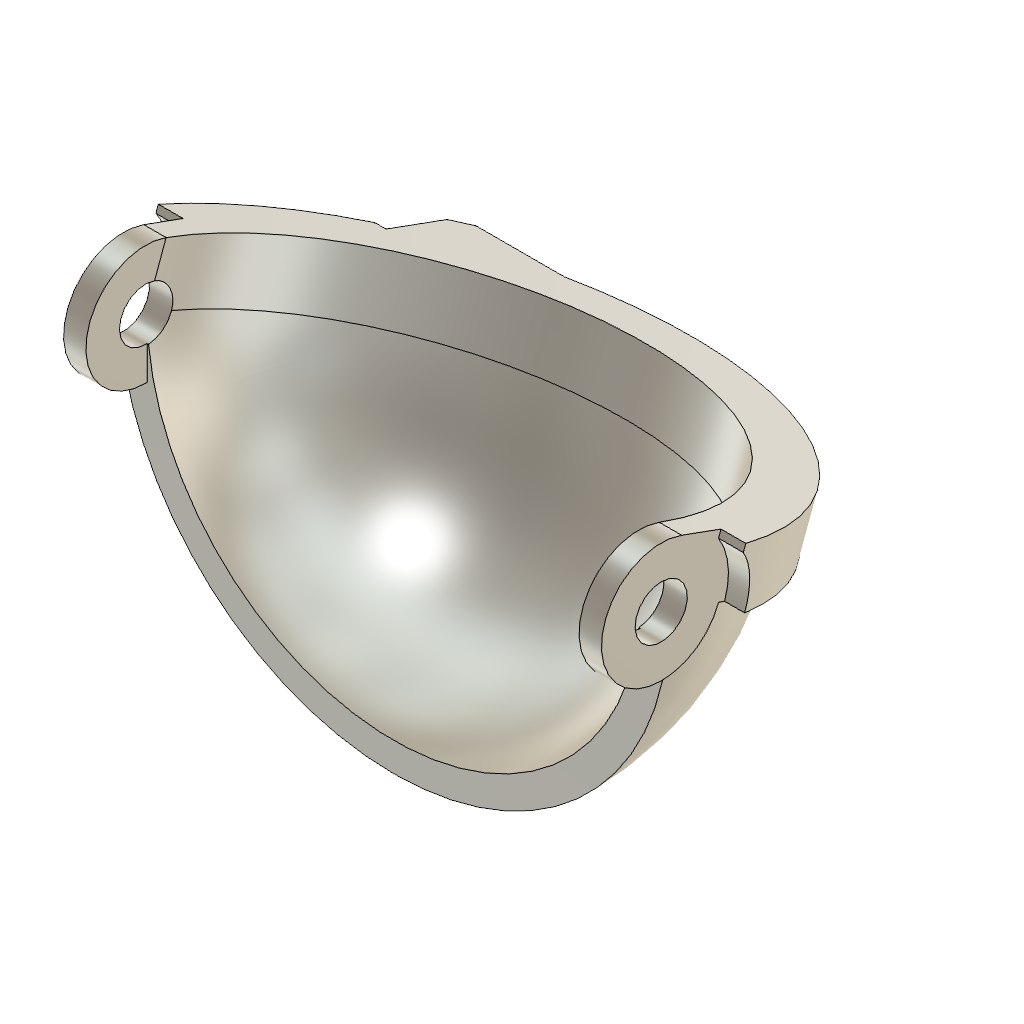
Top Left Lid native (Autodesk Fusion 360 design; units mm, degrees)
part number: 2026-10-13-22-57-52-856
Autodesk Fusion 360 part; units mm, degrees
ref_plane "WorkPlane1" through (0, 0, 2.0171) normal (0, 0, 1) x (1, 0, 0)
sketch "Lip ring" plane through (0, 0, 2.0171) normal (0, 0, 1) x (1, 0, 0)
  circle A0 centre (0, 0) radius 19.858
  dimension "d63" = 39.716
  constraint coincident A0.centre origin
  measures "d63" diameter of A0
extrude "Lip ring (1)" add sketch "Lip ring" along normal mid plane 3.9658
ref_plane "WorkPlane2" through (0, 0, 2.0171) normal (0, 0, 1) x (1, 0, 0)
sketch "Ring bore" plane through (0, 0, 2.0171) normal (0, 0, 1) x (1, 0, 0)
  circle A0 centre (0, 0.094) radius 16.5
  dimension "d64" = 33
  dimension "d65" = 0.094
  constraint vertical origin A0.centre
  measures "d64" diameter of A0
  measures "d65" vertical distance of origin A0.centre
extrude "Ring bore (1)" cut sketch "Ring bore" along normal mid plane 4.9658
ref_plane "WorkPlane3" through (0, 0.094, 0) normal (0, 1, 0) x (0, 0, 1)
sketch "Shell" plane through (0, 0.094, 0) normal (0, 1, 0) x (1, 0, 0)
  line L0 (16.5, -0.5342) -> (18.435, -0.5342)
  line L1 (18.435, -0.5342) -> (18.435, -0.0342)
  arc A0 (18.435, -0.0342) -> (0, 18.4008) centre (0, -0.0342) ccw
  line L2 (0, 18.4008) -> (0, 16.4658)
  arc A1 (16.5, -0.0342) -> (0, 16.4658) centre (0, -0.0342) ccw
  line L3 (16.5, -0.0342) -> (16.5, -0.5342)
  line L4 (0, 18.4008) -> (0, -0.5342) construction
  dimension "d66" = 18.435
  dimension "d67" = 16.5
  dimension "d68" = 0.0342
  dimension "d69" = 0.5342
  dimension "d70" = 18.4008
  dimension "d71" = 0.5342
  constraint horizontal L0
  constraint vertical L1
  constraint vertical L2
  constraint vertical L3
  constraint vertical L4
  constraint tangent L1 A0
  constraint tangent A1 L3
  constraint coincident A0.centre A1.centre
  constraint vertical origin A0.centre
  constraint vertical origin A0.end
  measures "d66" radius of A0
  measures "d67" radius of A1
  measures "d68" vertical distance of origin A0.centre
  measures "d69" vertical distance of origin L0.start
  measures "d70" vertical distance of origin A0.end
  measures "d71" vertical distance of origin L4.end
revolve "Shell (1)" add sketch "Shell" angle 360 about axis through (0, 0.094, -18.4008) along (0, 0, 1)
sketch "Shell trim y0.1" plane through (0, 0, 0) normal (1, 0, 0) x (0, 0, -1)
  line L0 (25, 9.2057) -> (-25, -8.9928)
  line L1 (-25, -8.9928) -> (-25, -30)
  line L2 (-25, -30) -> (25, -30)
  line L3 (25, -30) -> (25, 9.2057)
  dimension "d72" = 25
  dimension "d73" = 9.2057
  dimension "d74" = 25
  dimension "d75" = 8.9928
  dimension "d76" = 30
  constraint vertical L1
  constraint horizontal L2
  constraint vertical L3
  measures "d72" horizontal distance of origin L0.start
  measures "d73" vertical distance of origin L0.start
  measures "d74" horizontal distance of origin L0.end
  measures "d75" vertical distance of origin L0.end
  measures "d76" vertical distance of origin L1.end
extrude "Shell trim y0.1 (1)" cut sketch "Shell trim y0.1" along normal mid plane 42
ref_plane "WorkPlane4" through (0, 0, 2.0171) normal (0, 0, 1) x (1, 0, 0)
sketch "Ring half" plane through (0, 0, 2.0171) normal (0, 0, 1) x (1, 0, 0)
  line L0 (-21, 0) -> (21, 0)
  line L1 (21, 0) -> (21, -21)
  line L2 (21, -21) -> (-21, -21)
  line L3 (-21, -21) -> (-21, 0)
  dimension "d77" = 21
  dimension "d78" = 21
  dimension "d79" = 21
  constraint horizontal L0
  constraint vertical L1
  constraint horizontal L2
  constraint vertical L3
  constraint horizontal origin L0.start
  measures "d77" horizontal distance of origin L0.start
  measures "d78" horizontal distance of origin L0.end
  measures "d79" vertical distance of origin L1.end
extrude "Ring half (1)" cut sketch "Ring half" along normal mid plane 4.9658
ref_plane "WorkPlane5" through (19.5, 0, 0) normal (1, 0, 0) x (0, 1, 0)
sketch "Past ear R" plane through (19.5, 0, 0) normal (1, 0, 0) x (0, 0, -1)
  line L0 (6, -6) -> (6, 2.8)
  line L1 (6, 2.8) -> (3.5228, 2.8)
  arc A0 (3.5228, 2.8) -> (-3.5228, 2.8) centre (0, 0) ccw
  line L2 (-3.5228, 2.8) -> (-4.5, 2.8)
  line L3 (-4.5, 2.8) -> (-4.5, -6)
  line L4 (-4.5, -6) -> (6, -6)
  dimension "d80" = 4.5
  dimension "d81" = 6
  dimension "d82" = 6
  dimension "d83" = 2.8
  dimension "d84" = 3.5228
  dimension "d85" = 4.5
  constraint vertical L0
  constraint horizontal L1
  constraint horizontal L2
  constraint vertical L3
  constraint horizontal L4
  constraint coincident A0.centre origin
  measures "d80" radius of A0
  measures "d81" horizontal distance of A0.centre L0.start
  measures "d82" vertical distance of A0.centre L0.start
  measures "d83" vertical distance of A0.centre L0.end
  measures "d84" horizontal distance of A0.centre A0.end
  measures "d85" horizontal distance of A0.centre L2.end
extrude "Past ear R (1)" cut sketch "Past ear R" along normal mid plane 3
ref_plane "WorkPlane6" through (-19.5, 0, 0) normal (1, 0, 0) x (0, 1, 0)
sketch "Past ear L" plane through (-19.5, 0, 0) normal (1, 0, 0) x (0, 0, -1)
  line L0 (6, -6) -> (6, 2.8)
  line L1 (6, 2.8) -> (3.5228, 2.8)
  arc A0 (3.5228, 2.8) -> (-3.5228, 2.8) centre (0, 0) ccw
  line L2 (-3.5228, 2.8) -> (-4.5, 2.8)
  line L3 (-4.5, 2.8) -> (-4.5, -6)
  line L4 (-4.5, -6) -> (6, -6)
  dimension "d86" = 4.5
  dimension "d87" = 6
  dimension "d88" = 6
  dimension "d89" = 2.8
  dimension "d90" = 3.5228
  dimension "d91" = 4.5
  constraint vertical L0
  constraint horizontal L1
  constraint horizontal L2
  constraint vertical L3
  constraint horizontal L4
  constraint coincident A0.centre origin
  measures "d86" radius of A0
  measures "d87" horizontal distance of A0.centre L0.start
  measures "d88" vertical distance of A0.centre L0.start
  measures "d89" vertical distance of A0.centre L0.end
  measures "d90" horizontal distance of A0.centre A0.end
  measures "d91" horizontal distance of A0.centre L2.end
extrude "Past ear L (1)" cut sketch "Past ear L" along normal mid plane 3
ref_plane "WorkPlane7" through (17.25, 0, 0) normal (1, 0, 0) x (0, 1, 0)
sketch "Ear R" plane through (17.25, 0, 0) normal (1, 0, 0) x (0, 0, -1)
  circle A0 centre (0, 0) radius 4
  dimension "d92" = 8
  constraint coincident A0.centre origin
  measures "d92" diameter of A0
extrude "Ear R (1)" add sketch "Ear R" along normal mid plane 1.5
ref_plane "WorkPlane8" through (-17.25, 0, 0) normal (1, 0, 0) x (0, 1, 0)
sketch "Ear L" plane through (-17.25, 0, 0) normal (1, 0, 0) x (0, 0, -1)
  circle A0 centre (0, 0) radius 4
  dimension "d93" = 8
  constraint coincident A0.centre origin
  measures "d93" diameter of A0
extrude "Ear L (1)" add sketch "Ear L" along normal mid plane 1.5
ref_plane "WorkPlane9" through (17.25, 0, 0) normal (1, 0, 0) x (0, 1, 0)
sketch "Ear hole R" plane through (17.25, 0, 0) normal (1, 0, 0) x (0, 0, -1)
  circle A0 centre (0, 0) radius 1.75
  dimension "d94" = 3.5
  constraint coincident A0.centre origin
  measures "d94" diameter of A0
extrude "Ear hole R (1)" cut sketch "Ear hole R" along normal mid plane 2.5
ref_plane "WorkPlane10" through (-17.25, 0, 0) normal (1, 0, 0) x (0, 1, 0)
sketch "Ear hole L" plane through (-17.25, 0, 0) normal (1, 0, 0) x (0, 0, -1)
  circle A0 centre (0, 0) radius 1.75
  dimension "d95" = 3.5
  constraint coincident A0.centre origin
  measures "d95" diameter of A0
extrude "Ear hole L (1)" cut sketch "Ear hole L" along normal mid plane 2.5
ref_plane "WorkPlane11" through (0, 0, 2.0171) normal (0, 0, 1) x (1, 0, 0)
sketch "Tab notch" plane through (0, 0, 2.0171) normal (0, 0, 1) x (1, 0, 0)
  line L0 (-14.1348, 13.1481) -> (-21, 13.1481)
  line L1 (-21, 13.1481) -> (-21, 21)
  line L2 (-21, 21) -> (-14.1348, 21)
  line L3 (-14.1348, 21) -> (-14.1348, 13.1481)
  dimension "d96" = 14.1348
  dimension "d97" = 13.1481
  dimension "d98" = 21
  dimension "d99" = 21
  constraint horizontal L0
  constraint vertical L1
  constraint horizontal L2
  constraint vertical L3
  measures "d96" horizontal distance of origin L0.start
  measures "d97" vertical distance of origin L0.start
  measures "d98" horizontal distance of origin L0.end
  measures "d99" vertical distance of origin L1.end
extrude "Tab notch (1)" cut sketch "Tab notch" along normal mid plane 4.9658
ref_plane "WorkPlane12" through (0, 0, 2.0171) normal (0, 0, 1) x (1, 0, 0)
sketch "Tab" plane through (0, 0, 2.0171) normal (0, 0, 1) x (1, 0, 0)
  line L0 (-14.1348, 13.1481) -> (-14.1348, 17.5)
  line L1 (-14.1348, 17.5) -> (-13.1348, 18.5)
  line L2 (-13.1348, 18.5) -> (-6, 18.5)
  line L3 (-6, 18.5) -> (-14.1348, 13.1481)
  dimension "d100" = 14.1348
  dimension "d101" = 13.1481
  dimension "d102" = 17.5
  dimension "d103" = 13.1348
  dimension "d104" = 18.5
  dimension "d105" = 6
  constraint vertical L0
  constraint horizontal L2
  measures "d100" horizontal distance of origin L0.start
  measures "d101" vertical distance of origin L0.start
  measures "d102" vertical distance of origin L0.end
  measures "d103" horizontal distance of origin L1.end
  measures "d104" vertical distance of origin L1.end
  measures "d105" horizontal distance of origin L2.end
extrude "Tab (1)" add sketch "Tab" along normal mid plane 3.9658
ref_plane "WorkPlane13" through (-11.3848, 0, 0) normal (1, 0, 0) x (0, 1, 0)
sketch "Tab pin hole" plane through (-11.3848, 0, 0) normal (1, 0, 0) x (0, 0, -1)
  circle A0 centre (-2.0171, 16) radius 1
  dimension "d106" = 2
  dimension "d107" = 2.0171
  dimension "d108" = 16
  measures "d106" diameter of A0
  measures "d107" horizontal distance of origin A0.centre
  measures "d108" vertical distance of origin A0.centre
extrude "Tab pin hole (1)" cut sketch "Tab pin hole" along normal mid plane 6.5
ref_plane "WorkPlane14" through (15, 0, 0) normal (1, 0, 0) x (0, 1, 0)
sketch "Pocket" plane through (15, 0, 0) normal (1, 0, 0) x (0, 0, -1)
  circle A0 centre (-0.5, 6.982) radius 1
  dimension "d109" = 2
  dimension "d110" = 0.5
  dimension "d111" = 6.982
  measures "d109" diameter of A0
  measures "d110" horizontal distance of origin A0.centre
  measures "d111" vertical distance of origin A0.centre
extrude "Pocket (1)" cut sketch "Pocket" along normal mid plane 3
ref_plane "WorkPlane15" through (0, 0, 0.5) normal (0, 0, 1) x (1, 0, 0)
sketch "Pocket floor" plane through (0, 0, 0.5) normal (0, 0, 1) x (1, 0, 0)
  line L0 (16.5962, 4.5409) -> (17.7247, 4.8433)
  arc A0 (17.7247, 4.8433) -> (15.5617, 9.818) centre (0, 0.094) ccw
  line L1 (15.5617, 9.818) -> (14.5708, 9.1988)
  arc A1 (16.5962, 4.5409) -> (14.5708, 9.1988) centre (0, 0.094) ccw
  dimension "d112" = 18.35
  dimension "d113" = 17.1816
  dimension "d114" = 0.094
  dimension "d115" = 16.5962
  dimension "d116" = 17.7247
  dimension "d117" = 15.5617
  dimension "d118" = 14.5708
  constraint coincident A0.centre A1.centre
  constraint vertical origin A0.centre
  measures "d112" radius of A0
  measures "d113" radius of A1
  measures "d114" vertical distance of origin A0.centre
  measures "d115" horizontal distance of origin L0.start
  measures "d116" horizontal distance of origin L0.end
  measures "d117" horizontal distance of origin A0.end
  measures "d118" horizontal distance of origin L1.end
extrude "Pocket floor (1)" add sketch "Pocket floor" along normal mid plane 2
move_body "Frame x -20 deg" bodies 1 to x (1, 0, 0) y (0, 0.939693, -0.34202) z (0, 0.34202, 0.939693) at (0, 0, 0)
named bodies: "Top Left Lid native"
